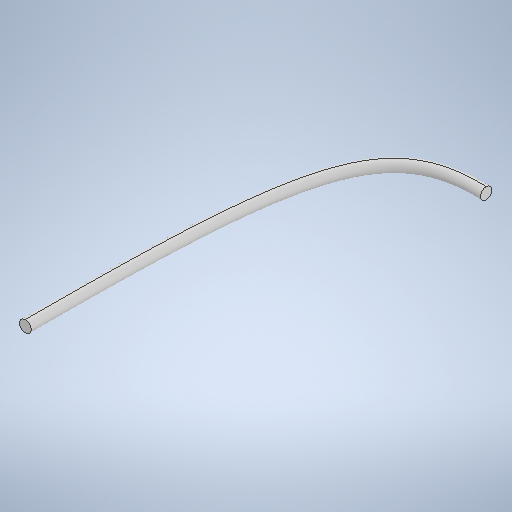
# Autodesk Inventor part: Bracito
Saved by Autodesk Inventor 2025.2 (Build 292293000, 293)
## iProperties
Created: 2025-05-16
Part Number: Bracito
Material: Generic
Document SubType Name: Modeling
Designer: laura
Density: 1 g/cm^3
Appearance: Default
Author: laura
Autodesk Inventor part; units mm, degrees
ref_plane "YZ Plane" through (0, 0, 0) normal (1, 0, 0) x (0, 1, 0)
ref_plane "XZ Plane" through (0, 0, 0) normal (0, 1, 0) x (-1, 0, 0)
ref_plane "XY Plane" through (0, 0, 0) normal (0, 0, 1) x (1, 0, 0)
sketch "Sketch1" plane through (0, 0, 0) normal (0, 1, 0) x (-1, 0, 0)
  spline S0 degree 3 poles (0, 0) (8.6189, -0.2568) (10.0234, 5.449) (10, 30) knots 0 0 0 0 1 1 1 1
  point P0 (5, 1)
  point P1 (8, 5)
  dimension "d0" = 5
  dimension "d1" = 8
  dimension "d2" = 10
  dimension "d3" = 1
  dimension "d4" = 5
  dimension "d5" = 30
  constraints: 4 other
  measures "d0" horizontal distance of point (5, 1) point (0, 0)
  measures "d1" horizontal distance of point (0, 0) point (8, 5)
  measures "d2" horizontal distance of point (0, 0) point (10, 30)
  measures "d3" vertical distance of point (5, 1) point (0, 0)
  measures "d4" vertical distance of point (8, 5) point (0, 0)
  measures "d5" vertical distance of point (10, 30) point (0, 0)
sketch "Sketch2" plane through (0, 0, 0) normal (1, 0, 0) x (0, 1, 0)
  circle A0 centre (0, 0) radius 0.5
  dimension "d6" = 1
  constraints: 1 centre point, 1 coincident
  measures "d6" diameter of A0
sweep "Sweep1" add profiles "Sketch2" path "Sketch1"
body "Solid1"
